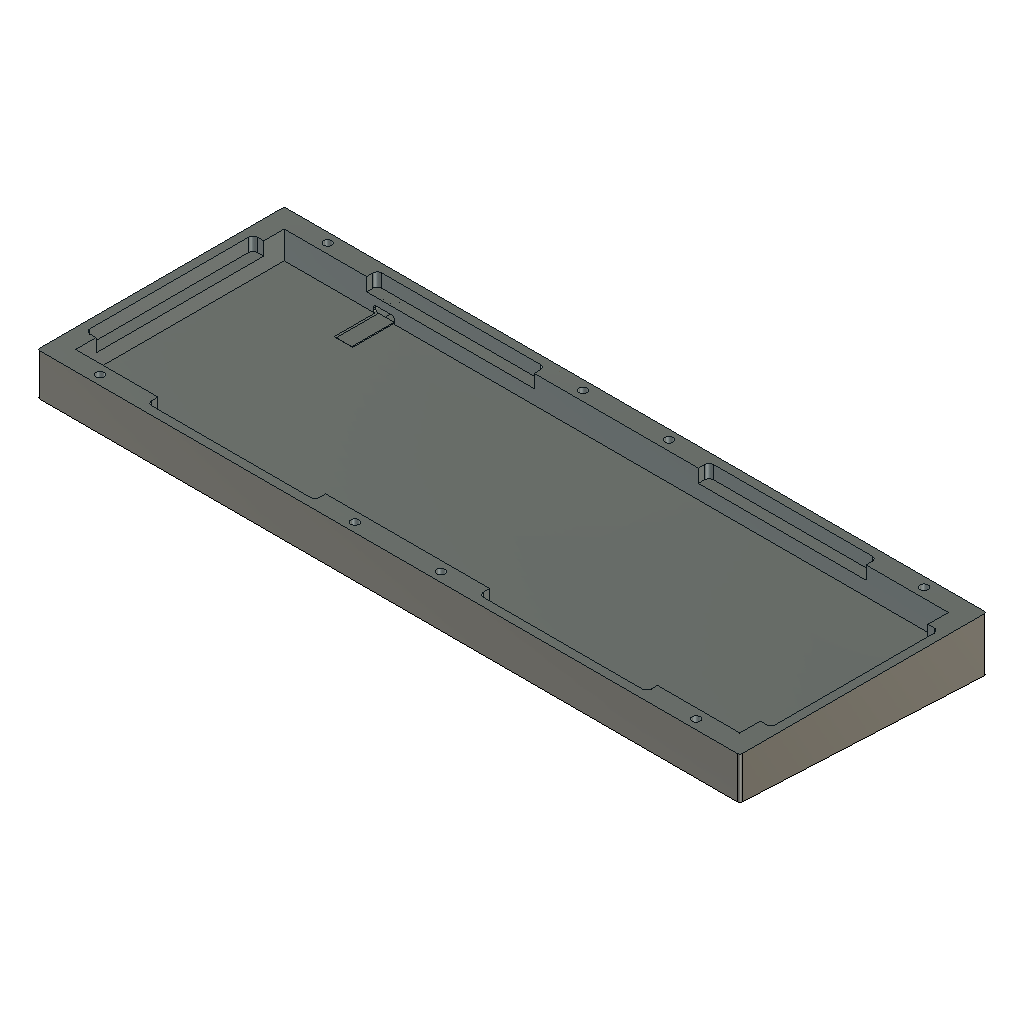
caseBottom (Autodesk Fusion 360 design; units mm, degrees)
Autodesk Fusion 360 part; units mm, degrees
sketch "case" plane through (0, 0, 0) normal (0, 0, 1) x (1, 0, 0)
  line L0 (-12.3912, 10.95) -> (-12.3912, 8.35)
  line L1 (-46.935, 8.35) -> (-12.3912, 8.35)
  line L2 (-46.935, -0.235) -> (-46.935, 8.35)
  line L3 (-46.935, -0.235) -> (-49.535, -0.235)
  arc A0 (-49.535, -0.235) -> (-51.435, -2.135) centre (-49.535, -2.135) ccw
  line L4 (-51.435, -2.135) -> (-51.435, -68.635)
  arc A1 (-51.435, -68.635) -> (-49.535, -70.535) centre (-49.535, -68.635) ccw
  line L5 (-49.535, -70.535) -> (-46.935, -70.535)
  line L6 (-46.935, -70.535) -> (-46.935, -79.12)
  line L7 (-46.935, -79.12) -> (-12.3913, -79.12)
  line L8 (-12.3913, -81.72) -> (-12.3913, -79.12)
  arc A2 (-12.3913, -81.72) -> (-10.4913, -83.62) centre (-10.4913, -81.72) ccw
  line L9 (56.0087, -83.62) -> (-10.4913, -83.62)
  arc A3 (56.0087, -83.62) -> (57.9087, -81.72) centre (56.0087, -81.72) ccw
  line L10 (57.9087, -79.12) -> (57.9087, -81.72)
  line L11 (92.3025, -79.12) -> (57.9087, -79.12)
  line L12 (126.6962, -79.12) -> (92.3025, -79.12)
  line L13 (126.6962, -81.72) -> (126.6962, -79.12)
  arc A4 (126.6962, -81.72) -> (128.5962, -83.62) centre (128.5962, -81.72) ccw
  line L14 (195.0962, -83.62) -> (128.5962, -83.62)
  arc A5 (195.0962, -83.62) -> (196.9963, -81.72) centre (195.0962, -81.72) ccw
  line L15 (196.9963, -79.12) -> (196.9962, -81.72)
  line L16 (196.9963, -79.12) -> (231.54, -79.12)
  line L17 (231.54, -70.535) -> (231.54, -79.12)
  line L18 (231.54, -70.535) -> (234.14, -70.535)
  arc A6 (234.14, -70.535) -> (236.04, -68.635) centre (234.14, -68.635) ccw
  line L19 (236.04, -68.635) -> (236.04, -2.135)
  arc A7 (236.04, -2.135) -> (234.14, -0.235) centre (234.14, -2.135) ccw
  line L20 (234.14, -0.235) -> (231.54, -0.235)
  line L21 (231.54, -0.235) -> (231.54, 8.35)
  line L22 (196.9962, 8.35) -> (231.54, 8.35)
  line L23 (196.9963, 10.95) -> (196.9962, 8.35)
  arc A8 (196.9963, 10.95) -> (195.0962, 12.85) centre (195.0962, 10.95) ccw
  line L24 (128.5963, 12.85) -> (195.0962, 12.85)
  arc A9 (128.5963, 12.85) -> (126.6963, 10.95) centre (128.5963, 10.95) ccw
  line L25 (126.6963, 8.35) -> (126.6963, 10.95)
  line L26 (92.3025, 8.35) -> (126.6963, 8.35)
  line L27 (57.9088, 8.35) -> (92.3025, 8.35)
  line L28 (57.9088, 8.35) -> (57.9088, 10.95)
  arc A10 (57.9088, 10.95) -> (56.0088, 12.85) centre (56.0088, 10.95) ccw
  line L29 (56.0088, 12.85) -> (-10.4912, 12.85)
  arc A11 (-10.4912, 12.85) -> (-12.3912, 10.95) centre (-10.4912, 10.95) ccw
  line L30 (-46.935, -0.235) -> (-46.935, -70.535)
  line L31 (-12.3913, -79.12) -> (57.9087, -79.12)
  line L32 (126.6962, -79.12) -> (196.9963, -79.12)
  line L33 (231.54, -70.535) -> (231.54, -0.235)
  line L34 (196.9962, 8.35) -> (126.6963, 8.35)
  line L35 (57.9088, 8.35) -> (-12.3912, 8.35)
  line L36 (196.9962, 16.35) -> (126.6963, 16.35)
  line L37 (92.3025, 16.35) -> (126.6963, 16.35)
  line L38 (57.9087, 16.35) -> (92.3025, 16.35)
  line L39 (57.9087, 16.35) -> (-12.3912, 16.35)
  line L40 (-53.935, 16.35) -> (-12.3912, 16.35)
  line L41 (-54.935, -0.235) -> (-54.935, 15.35)
  line L42 (-54.935, -0.235) -> (-54.935, -70.535)
  line L43 (-54.935, -70.535) -> (-54.935, -86.12)
  line L44 (-53.935, -87.12) -> (-12.3913, -87.12)
  line L45 (-12.3913, -87.12) -> (57.9087, -87.12)
  line L46 (92.3025, -87.12) -> (57.9087, -87.12)
  line L47 (126.6963, -87.12) -> (92.3025, -87.12)
  line L48 (126.6963, -87.12) -> (196.9963, -87.12)
  line L49 (196.9963, -87.12) -> (238.54, -87.12)
  line L50 (239.54, -70.535) -> (239.54, -86.12)
  line L51 (239.54, -70.535) -> (239.54, -0.235)
  line L52 (239.54, -0.235) -> (239.54, 15.35)
  line L53 (196.9962, 16.35) -> (238.54, 16.35)
  arc A12 (-53.935, 16.35) -> (-54.935, 15.35) centre (-53.935, 15.35) ccw
  arc A13 (-54.935, -86.12) -> (-53.935, -87.12) centre (-53.935, -86.12) ccw
  arc A14 (238.54, -87.12) -> (239.54, -86.12) centre (238.54, -86.12) ccw
  arc A15 (239.54, 15.35) -> (238.54, 16.35) centre (238.54, 15.35) ccw
  dimension "d40" = 8
  dimension "d41" = 8
  dimension "d42" = 8
  dimension "d43" = 8
  dimension "d44" = 8
  dimension "d45" = 8
  dimension "d46" = 8
  dimension "d47" = 8
  dimension "d48" = 8
  dimension "d49" = 8
  dimension "d50" = 8
  dimension "d51" = 8
  dimension "d52" = 8
  dimension "d53" = 8
  dimension "d54" = 8
  dimension "d55" = 8
  dimension "d56" = 8
  dimension "d57" = 8
  dimension "d58" = 1
  dimension "d59" = 1
  dimension "d60" = 1
  dimension "d61" = 1
  constraint coincident L2.start L3.start
  constraint coincident L5.end L6.start
  constraint coincident L7.end L8.end
  constraint coincident L10.start L11.end
  constraint coincident L12.start L13.end
  constraint coincident L15.start L16.start
  constraint coincident L17.start L18.start
  constraint coincident L20.end L21.start
  constraint coincident L22.start L23.end
  constraint coincident L25.start L26.end
  constraint coincident L27.start L28.start
  constraint coincident L0.end L1.end
  constraint tangent L40 A12
  constraint tangent L41 A12
  constraint tangent L43 A13
  constraint tangent L44 A13
  constraint tangent L49 A14
  constraint tangent L50 A14
  constraint tangent L53 A15
  constraint tangent L52 A15
  measures "d40" distance of L34 L36
  measures "d41" distance of L26 L37
  measures "d42" distance of L27 L38
  measures "d43" distance of L35 L39
  measures "d44" distance of L1 L40
  measures "d45" distance of L2 L41
  measures "d46" distance of L30 L42
  measures "d47" distance of L6 L43
  measures "d48" distance of L7 L44
  measures "d49" distance of L31 L45
  measures "d50" distance of L11 L46
  measures "d51" distance of L12 L47
  measures "d52" distance of L32 L48
  measures "d53" distance of L16 L49
  measures "d54" distance of L17 L50
  measures "d55" distance of L33 L51
  measures "d56" distance of L21 L52
  measures "d57" distance of L22 L53
  measures "d58" radius of A12
  measures "d59" radius of A13
  measures "d60" radius of A14
  measures "d61" radius of A15
extrude "Extrude1" add sketch "case" against normal blind 17 contours L0 L28 A10 L29 A11 L35 | L1 L2 L6 L7 L11 L12 L16 L17 L21 L22 L26 L27 L30 L31 L32 L33 L34 L35 | L3 A0 L4 A1 L5 L30 | L23 A8 L24 A9 L25 L34 | L8 A2 L9 A3 L10 L31 | L18 A6 L19 A7 L20 L33 | L13 A4 L14 A5 L15 L32 | L36 L37 L38 L39 L40 L41 L42 L43 L44 L45 L46 L47 L48 L49 L50 L51 L52 L53 A12 A13 A14 A15
sketch "caseSlantCut" plane through (-54.935, 0, 0) normal (-1, 0, 0) x (0, -1, 0)
  line L0 (86.12, 0) -> (-15.35, 0)
  line L1 (-15.35, 0) -> (-15.35, -17)
  line L2 (-15.35, -17) -> (86.12, -17)
  line L3 (86.12, -17) -> (86.12, 0)
  line L4 (-16.35, -17) -> (87.12, -17)
  line L5 (87.12, -17) -> (87.12, -12)
  line L6 (-16.35, -17) -> (87.12, -12)
  point P0 (35.385, -17)
  dimension "d64" = 103.47
  dimension "d65" = 5
  constraint midpoint L4 P0
  constraint coincident L2 P0
  constraint coincident L2 L4.end
  constraint perpendicular L4 L5
  measures "d64" distance of L4.start L4.end
  measures "d65" distance of L4.end L5.end
extrude "Extrude2" cut sketch "caseSlantCut" against normal blind 350 contours L3 L4 L5 L6 | L1 L2 L3 L4 L6
extrude "Extrude3" cut sketch "case" against normal blind 6 contours L1 L2 L6 L7 L11 L12 L16 L17 L21 L22 L26 L27 L30 L31 L32 L33 L34 L35
extrude "Extrude4" add sketch "case" along normal blind 5.55
sketch "usbcCut" plane through (0, 16.35, 0) normal (0, 1, 0) x (-1, 0, 0)
  line L0 (-238.54, 5.55) -> (-238.54, -17)
  line L1 (-238.54, -17) -> (53.935, -17)
  line L2 (53.935, -17) -> (53.935, 5.55)
  line L3 (53.935, 5.55) -> (-238.54, 5.55)
  line L4 (-92.3025, 0.43) -> (5.0505, 0.43) construction
  line L5 (5.0505, 0.43) -> (5.0505, -4.67) construction
  line L6 (8.2905, -5.95) -> (1.8105, -5.95)
  line L7 (0.8805, -5.02) -> (0.8805, -4.32)
  line L8 (1.8105, -3.39) -> (8.2905, -3.39)
  line L9 (9.2205, -4.32) -> (9.2205, -5.02)
  line L10 (9.2205, -5.95) -> (0.8805, -3.39) construction
  line L11 (0.8805, -5.95) -> (9.2205, -3.39) construction
  arc A0 (1.8105, -3.39) -> (0.8805, -4.32) centre (1.8105, -4.32) ccw
  arc A1 (0.8805, -5.02) -> (1.8105, -5.95) centre (1.8105, -5.02) ccw
  arc A2 (9.2205, -4.32) -> (8.2905, -3.39) centre (8.2905, -4.32) ccw
  arc A3 (8.2905, -5.95) -> (9.2205, -5.02) centre (8.2905, -5.02) ccw
  arc A4 (9.4705, -4.32) -> (8.2905, -3.14) centre (8.2905, -4.32) ccw
  line L12 (1.8105, -3.14) -> (8.2905, -3.14)
  arc A5 (1.8105, -3.14) -> (0.6305, -4.32) centre (1.8105, -4.32) ccw
  line L13 (0.6305, -5.02) -> (0.6305, -4.32)
  arc A6 (0.6305, -5.02) -> (1.8105, -6.2) centre (1.8105, -5.02) ccw
  line L14 (8.2905, -6.2) -> (1.8105, -6.2)
  arc A7 (8.2905, -6.2) -> (9.4705, -5.02) centre (8.2905, -5.02) ccw
  line L15 (9.4705, -4.32) -> (9.4705, -5.02)
  arc A8 (12.2705, -4.32) -> (8.2905, -0.34) centre (8.2905, -4.32) ccw
  line L16 (1.8105, -0.34) -> (8.2905, -0.34)
  arc A9 (1.8105, -0.34) -> (-2.1695, -4.32) centre (1.8105, -4.32) ccw
  line L17 (-2.1695, -5.02) -> (-2.1695, -4.32)
  arc A10 (-2.1695, -5.02) -> (1.8105, -9) centre (1.8105, -5.02) ccw
  line L18 (8.2905, -9) -> (1.8105, -9)
  arc A11 (8.2905, -9) -> (12.2705, -5.02) centre (8.2905, -5.02) ccw
  line L19 (12.2705, -4.32) -> (12.2705, -5.02)
  point P0 (5.0505, -4.67)
  dimension "d72" = 97.353
  dimension "d73" = 5.1
  dimension "d75" = 8.34
  dimension "d76" = 2.56
  dimension "d79" = 0.7
  dimension "d80" = 0.7
  dimension "d81" = -0.25
  dimension "d82" = -2.8
  constraint parallel L3 L4
  constraint perpendicular L4 L5
  constraint horizontal L6
  constraint perpendicular L6 L7
  constraint parallel L6 L8
  constraint parallel L7 L9
  constraint coincident L10 P0
  constraint coincident L11 P0
  constraint coincident P0 L5.end
  constraint coincident L10.end L8
  constraint coincident L10.end L7
  constraint tangent L8 A0
  constraint tangent L7 A0
  constraint coincident L11.start L7
  constraint coincident L11.start L6
  constraint tangent L7 A1
  constraint tangent L6 A1
  constraint equal A0 A1
  constraint coincident L11.end L8
  constraint coincident L11.end L9
  constraint tangent L8 A2
  constraint tangent L9 A2
  constraint equal A0 A2
  constraint coincident L10.start L9
  constraint coincident L10.start L6
  constraint tangent L9 A3
  constraint tangent L6 A3
  measures "d72" distance of L4.start L4.end
  measures "d73" distance of L4 P0
  measures "d75" distance of L10.end L11.end
  measures "d76" distance of L11.start L10.end
  measures "d79" distance of L7.end L7.start
  measures "d80" distance of L9.start L9.end
extrude "Extrude5" cut sketch "usbcCut" against normal blind 20 contours L6 L7 L8 L9 A0 A1 A2 A3 | A4 L12 A5 L13 A6 L14 A7 L15
extrude "Extrude6" cut sketch "usbcCut" against normal blind 25 contours L6 L7 L8 L9 A0 A1 A2 A3 | A4 L12 A5 L13 A6 L14 A7 L15
sketch "Sketch4" plane through (0, 16.35, 0) normal (0, 1, 0) x (-1, 0, 0)
sketch "Sketch5" plane through (0, 0, 0) normal (0, 0, 1) x (1, 0, 0)
  line L0 (-8.9475, 8.35) -> (-8.9475, 9.29)
  dimension "d87" = 0.94
  constraint vertical L0
  measures "d87" distance of L0.start L0.end
extrude "Extrude7" cut sketch "usbcCut" against normal blind 7.06 contours A8 L16 A9 L17 A10 L18 A11 L19
sketch "Sketch6" plane through (0, 0, 5.55) normal (0, 0, 1) x (-1, 0, 0)
  line L0 (-57.9088, -10.95) -> (-57.9088, -8.35)
  line L1 (-57.9088, -8.35) -> (-126.6963, -8.35)
  line L2 (-126.6963, -8.35) -> (-126.6963, -10.95)
  arc A0 (-128.5963, -12.85) -> (-126.6963, -10.95) centre (-128.5963, -10.95) ccw
  line L3 (-128.5963, -12.85) -> (-195.0962, -12.85)
  arc A1 (-196.9963, -10.95) -> (-195.0962, -12.85) centre (-195.0963, -10.95) ccw
  line L4 (-196.9963, -10.95) -> (-196.9962, -8.35)
  line L5 (-196.9962, -8.35) -> (-231.54, -8.35)
  line L6 (-231.54, -8.35) -> (-231.54, 0.235)
  line L7 (-231.54, 0.235) -> (-234.14, 0.235)
  arc A2 (-236.04, 2.135) -> (-234.14, 0.235) centre (-234.14, 2.135) ccw
  line L8 (-236.04, 2.135) -> (-236.04, 68.635)
  arc A3 (-234.14, 70.535) -> (-236.04, 68.635) centre (-234.14, 68.635) ccw
  line L9 (-234.14, 70.535) -> (-231.54, 70.535)
  line L10 (-231.54, 70.535) -> (-231.54, 79.12)
  line L11 (-231.54, 79.12) -> (-196.9963, 79.12)
  line L12 (-196.9963, 79.12) -> (-196.9962, 81.72)
  arc A4 (-195.0962, 83.62) -> (-196.9962, 81.72) centre (-195.0962, 81.72) ccw
  line L13 (-195.0962, 83.62) -> (-128.5962, 83.62)
  arc A5 (-126.6962, 81.72) -> (-128.5962, 83.62) centre (-128.5962, 81.72) ccw
  line L14 (-126.6962, 81.72) -> (-126.6962, 79.12)
  line L15 (-126.6962, 79.12) -> (-57.9087, 79.12)
  line L16 (-57.9087, 79.12) -> (-57.9087, 81.72)
  arc A6 (-56.0087, 83.62) -> (-57.9087, 81.72) centre (-56.0087, 81.72) ccw
  line L17 (-56.0087, 83.62) -> (10.4913, 83.62)
  arc A7 (12.3913, 81.72) -> (10.4913, 83.62) centre (10.4913, 81.72) ccw
  line L18 (12.3913, 81.72) -> (12.3913, 79.12)
  line L19 (12.3913, 79.12) -> (46.935, 79.12)
  line L20 (46.935, 79.12) -> (46.935, 70.535)
  line L21 (46.935, 70.535) -> (49.535, 70.535)
  arc A8 (51.435, 68.635) -> (49.535, 70.535) centre (49.535, 68.635) ccw
  line L22 (51.435, 68.635) -> (51.435, 2.135)
  arc A9 (49.535, 0.235) -> (51.435, 2.135) centre (49.535, 2.135) ccw
  line L23 (49.535, 0.235) -> (46.935, 0.235)
  line L24 (46.935, 0.235) -> (46.935, -8.35)
  line L25 (46.935, -8.35) -> (12.3912, -8.35)
  line L26 (12.3912, -8.35) -> (12.3912, -10.95)
  arc A10 (10.4912, -12.85) -> (12.3912, -10.95) centre (10.4912, -10.95) ccw
  line L27 (10.4912, -12.85) -> (-56.0088, -12.85)
  arc A11 (-57.9088, -10.95) -> (-56.0088, -12.85) centre (-56.0088, -10.95) ccw
  line L28 (-239.54, 86.12) -> (-239.54, -15.35)
  arc A12 (-239.54, -15.35) -> (-238.54, -16.35) centre (-238.54, -15.35) ccw
  line L29 (-238.54, -16.35) -> (53.935, -16.35)
  arc A13 (53.935, -16.35) -> (54.935, -15.35) centre (53.935, -15.35) ccw
  line L30 (54.935, -15.35) -> (54.935, 86.12)
  arc A14 (54.935, 86.12) -> (53.935, 87.12) centre (53.935, 86.12) ccw
  line L31 (53.935, 87.12) -> (-238.54, 87.12)
  arc A15 (-238.54, 87.12) -> (-239.54, 86.12) centre (-238.54, 86.12) ccw
  line L32 (-92.3025, -16.35) -> (-92.3025, 87.12) construction
  line L33 (32.6975, -16.35) -> (32.6975, 87.12) construction
  line L34 (-217.3025, -16.35) -> (-217.3025, 87.12) construction
  line L35 (-92.3025, 79.12) -> (-92.3025, 87.12) construction
  line L36 (32.6975, 83.12) -> (-217.3025, 83.12) construction
  line L37 (-92.3025, -16.35) -> (-92.3025, -8.35) construction
  line L38 (-217.3025, -12.4391) -> (32.6975, -12.4391) construction
  line L39 (-74.3025, -16.35) -> (-74.3025, 87.12) construction
  line L40 (-110.3025, 87.12) -> (-110.3025, -16.35) construction
  circle A16 centre (-74.3025, -12.4391) radius 1.7
  circle A17 centre (32.6975, -12.4391) radius 1.7
  circle A18 centre (32.6975, -12.4391) radius 2.85
  circle A19 centre (-74.3025, -12.4391) radius 2.85
  circle A20 centre (-110.3025, -12.4391) radius 2.85
  circle A21 centre (-110.3025, -12.4391) radius 1.7
  circle A22 centre (-217.3025, -12.4391) radius 2.85
  circle A23 centre (-217.3025, -12.4391) radius 1.7
  line L41 (-239.54, 35.385) -> (54.935, 35.385)
  circle A24 centre (32.6975, 83.2091) radius 1.7
  circle A25 centre (32.6975, 83.2091) radius 2.85
  circle A26 centre (-74.3025, 83.2091) radius 2.85
  circle A27 centre (-74.3025, 83.2091) radius 1.7
  circle A28 centre (-110.3025, 83.2091) radius 1.7
  circle A29 centre (-110.3025, 83.2091) radius 2.85
  circle A30 centre (-217.3025, 83.2091) radius 2.85
  circle A31 centre (-217.3025, 83.2091) radius 1.7
  point P0 (-92.3025, 83.12)
  point P1 (-92.3025, -12.4391)
  point P2 (-92.3025, 35.385)
  dimension "d90" = 125
  dimension "d91" = 125
  dimension "d98" = 18
  dimension "d99" = 18
  dimension "d100" = 3.4
  dimension "d103" = 3.4
  dimension "d104" = 5.7
  dimension "d105" = 5.7
  constraint midpoint L29 L32.start
  constraint midpoint L31 L32.end
  constraint coincident L29 L33.start
  constraint perpendicular L29 L33
  constraint coincident L31 L33.end
  constraint coincident L29 L34.start
  constraint perpendicular L29 L34
  constraint coincident L31 L34.end
  constraint coincident L15 L35.start
  constraint coincident L31 L32.end
  constraint perpendicular L31 L35
  constraint midpoint L36 P0
  constraint coincident L35 P0
  constraint coincident L34 L36.end
  constraint perpendicular L34 L36
  constraint coincident L33 L36.start
  constraint coincident L29 L32.start
  constraint coincident L1 L37.end
  constraint perpendicular L1 L37
  constraint midpoint L38 P1
  constraint coincident L37 P1
  constraint coincident L33 L38.end
  constraint perpendicular L33 L38
  constraint coincident L34 L38.start
  constraint coincident L29 L39.start
  constraint perpendicular L29 L39
  constraint coincident L31 L39.end
  constraint coincident L31 L40.start
  constraint perpendicular L31 L40
  constraint coincident L29 L40.end
  constraint coincident L39 A16.centre
  constraint coincident L38 A16.centre
  constraint coincident L38.end A17.centre
  constraint concentric A17 A18
  constraint concentric A16 A19
  constraint symmetric L32 A16 A21
  constraint symmetric L32 A17 A23
  constraint symmetric L32 A18 A22
  constraint symmetric L32 A19 A20
  constraint midpoint L41 P2
  constraint coincident L32 P2
  constraint coincident L30 L41.end
  constraint perpendicular L30 L41
  constraint symmetric A16 L41 A27
  constraint symmetric A17 L41 A24
  constraint symmetric A18 L41 A25
  constraint symmetric A19 L41 A26
  constraint symmetric A20 L41 A29
  constraint symmetric A21 L41 A28
  constraint symmetric A22 L41 A30
  constraint symmetric A23 L41 A31
  measures "d90" distance of L32 L33
  measures "d91" distance of L32 L34
  measures "d98" distance of L32 L39
  measures "d99" distance of L32 L40
  measures "d100" diameter of A16
  measures "d103" diameter of A17
  measures "d104" diameter of A18
  measures "d105" diameter of A19
fillet "Fillet1" radius 0.5 8 edges at (-11.1048, 16.35, -1.5057) (-12.2705, 16.35, -4.67) (-11.1048, 16.35, -7.8343) (-5.0505, 16.35, -9) (1.0038, 16.35, -7.8343) (2.1695, 16.35, -4.67) (1.0038, 16.35, -1.5057) (-5.0505, 16.35, -0.34)
extrude "Extrude8" cut sketch "Sketch6" against normal blind 40 contours A16 | A17 | A21 | A23 | A24 | A27 | A28 | A31
extrude "Extrude9" cut sketch "Sketch6" against normal blind 30 from surface at -15 contours A18 | A19 | A20 | A22 | A25 | A26 | A29 | A30
extrude "Extrude10" cut sketch "caseSlantCut" against normal blind 420 contours L3 L4 L5 L6 | L1 L2 L3 L4 L6 | L1 L4 L6
sketch "Sketch7" plane through (0, -0.7815, -16.1722) normal (0, -0.048267, -0.998834) x (1, 0, 0)
  line L0 (239.54, -16.1503) -> (239.54, 85.4381)
  ellipse E0 centre (238.54, 85.4381) end of major axis (238.54, 86.4393) minor radius 1 (239.54, 85.4381) -> (238.54, 86.4393) ccw
  line L1 (238.54, 86.4393) -> (-53.935, 86.4393)
  ellipse E1 centre (-53.935, 85.4381) end of major axis (-53.935, 84.4369) minor radius 1 (-53.935, 86.4393) -> (-54.935, 85.4381) ccw
  line L2 (-54.935, 85.4381) -> (-54.935, -16.1503)
  ellipse E2 centre (-53.935, -16.1503) end of major axis (-53.935, -17.1515) minor radius 1 (-54.935, -16.1503) -> (-53.935, -17.1515) ccw
  line L3 (-53.935, -17.1515) -> (238.54, -17.1515)
  ellipse E3 centre (238.54, -16.1503) end of major axis (238.54, -15.1491) minor radius 1 (238.54, -17.1515) -> (239.54, -16.1503) ccw
  ellipse E4 centre (74.3025, 82.5238) end of major axis (74.3025, 79.6705) minor radius 2.85
  ellipse E5 centre (217.3025, -13.236) end of major axis (217.3025, -16.0893) minor radius 2.85
  ellipse E6 centre (-32.6975, -13.236) end of major axis (-32.6975, -16.0893) minor radius 2.85
  ellipse E7 centre (217.3025, 82.5238) end of major axis (217.3025, 79.6705) minor radius 2.85
  ellipse E8 centre (-32.6975, 82.5238) end of major axis (-32.6975, 79.6705) minor radius 2.85
  ellipse E9 centre (110.3025, -13.236) end of major axis (110.3025, -16.0893) minor radius 2.85
  ellipse E10 centre (74.3025, -13.236) end of major axis (74.3025, -16.0893) minor radius 2.85
  ellipse E11 centre (110.3025, 82.5238) end of major axis (110.3025, 79.6705) minor radius 2.85
  line L4 (229.54, -7.1515) -> (229.54, 76.4393) construction
  line L5 (229.54, 76.4393) -> (-44.935, 76.4393) construction
  line L6 (-44.935, 76.4393) -> (-44.935, -7.1515) construction
  line L7 (-44.935, -7.1515) -> (229.54, -7.1515) construction
  circle A0 centre (229.54, 76.4393) radius 4
  circle A1 centre (-44.935, 76.4393) radius 4
  circle A2 centre (229.54, -7.1515) radius 4
  circle A3 centre (-44.935, -7.1515) radius 4
  dimension "d113" = -10
  dimension "d114" = 8
  dimension "d115" = 8
  dimension "d116" = 8
  dimension "d117" = 8
  constraint coincident L4.end L5.start
  constraint coincident L5.end L6.start
  constraint coincident L4.start L7.end
  constraint coincident L6.end L7.start
  measures "d114" diameter of A0
  measures "d115" diameter of A1
  measures "d116" diameter of A2
  measures "d117" diameter of A3
extrude "Extrude11" cut sketch "Sketch7" against normal blind 1 contours A0 | A1 | A2 | A3
chamfer "Chamfer1" distance 1 angle 45 1 edges at (-48.6643, 4.9169, -16.4475) tangent chain off
chamfer "Chamfer2" distance 1 angle 45 3 edges at (-48.6643, -78.5764, -12.4129) (225.8107, -78.5764, -12.4129) (225.8107, 4.9169, -16.4475) tangent chain off
sketch "Sketch8" plane through (0, 0, 5.55) normal (0, 0, 1) x (-1, 0, 0)
  line L0 (-239.54, 86.12) -> (-239.54, -15.35)
  arc A0 (-239.54, -15.35) -> (-238.54, -16.35) centre (-238.54, -15.35) ccw
  line L1 (-238.54, -16.35) -> (53.935, -16.35)
  arc A1 (53.935, -16.35) -> (54.935, -15.35) centre (53.935, -15.35) ccw
  line L2 (54.935, -15.35) -> (54.935, 86.12)
  arc A2 (54.935, 86.12) -> (53.935, 87.12) centre (53.935, 86.12) ccw
  line L3 (53.935, 87.12) -> (-238.54, 87.12)
  arc A3 (-238.54, 87.12) -> (-239.54, 86.12) centre (-238.54, 86.12) ccw
  line L4 (-57.9088, -10.95) -> (-57.9088, -8.35)
  line L5 (-57.9088, -8.35) -> (-126.6963, -8.35)
  line L6 (-126.6963, -8.35) -> (-126.6963, -10.95)
  arc A4 (-128.5963, -12.85) -> (-126.6963, -10.95) centre (-128.5963, -10.95) ccw
  line L7 (-128.5963, -12.85) -> (-195.0962, -12.85)
  arc A5 (-196.9963, -10.95) -> (-195.0962, -12.85) centre (-195.0963, -10.95) ccw
  line L8 (-196.9963, -10.95) -> (-196.9962, -8.35)
  line L9 (-196.9962, -8.35) -> (-231.54, -8.35)
  line L10 (-231.54, -8.35) -> (-231.54, 0.235)
  line L11 (-231.54, 0.235) -> (-234.14, 0.235)
  arc A6 (-236.04, 2.135) -> (-234.14, 0.235) centre (-234.14, 2.135) ccw
  line L12 (-236.04, 2.135) -> (-236.04, 68.635)
  arc A7 (-234.14, 70.535) -> (-236.04, 68.635) centre (-234.14, 68.635) ccw
  line L13 (-234.14, 70.535) -> (-231.54, 70.535)
  line L14 (-231.54, 70.535) -> (-231.54, 79.12)
  line L15 (-231.54, 79.12) -> (-196.9963, 79.12)
  line L16 (-196.9963, 79.12) -> (-196.9962, 81.72)
  arc A8 (-195.0962, 83.62) -> (-196.9962, 81.72) centre (-195.0962, 81.72) ccw
  line L17 (-195.0962, 83.62) -> (-128.5962, 83.62)
  arc A9 (-126.6962, 81.72) -> (-128.5962, 83.62) centre (-128.5962, 81.72) ccw
  line L18 (-126.6962, 81.72) -> (-126.6962, 79.12)
  line L19 (-126.6962, 79.12) -> (-57.9087, 79.12)
  line L20 (-57.9087, 79.12) -> (-57.9087, 81.72)
  arc A10 (-56.0087, 83.62) -> (-57.9087, 81.72) centre (-56.0087, 81.72) ccw
  line L21 (-56.0087, 83.62) -> (10.4913, 83.62)
  arc A11 (12.3913, 81.72) -> (10.4913, 83.62) centre (10.4913, 81.72) ccw
  line L22 (12.3913, 81.72) -> (12.3913, 79.12)
  line L23 (12.3913, 79.12) -> (46.935, 79.12)
  line L24 (46.935, 79.12) -> (46.935, 70.535)
  line L25 (46.935, 70.535) -> (49.535, 70.535)
  arc A12 (51.435, 68.635) -> (49.535, 70.535) centre (49.535, 68.635) ccw
  line L26 (51.435, 68.635) -> (51.435, 2.135)
  arc A13 (49.535, 0.235) -> (51.435, 2.135) centre (49.535, 2.135) ccw
  line L27 (49.535, 0.235) -> (46.935, 0.235)
  line L28 (46.935, 0.235) -> (46.935, -8.35)
  line L29 (46.935, -8.35) -> (12.3912, -8.35)
  line L30 (12.3912, -8.35) -> (12.3912, -10.95)
  arc A14 (10.4912, -12.85) -> (12.3912, -10.95) centre (10.4912, -10.95) ccw
  line L31 (10.4912, -12.85) -> (-56.0088, -12.85)
  arc A15 (-57.9088, -10.95) -> (-56.0088, -12.85) centre (-56.0088, -10.95) ccw
  circle A16 centre (32.6975, -12.4391) radius 1.7
  circle A17 centre (-217.3025, 83.2091) radius 1.7
  circle A18 centre (32.6975, 83.2091) radius 1.7
  circle A19 centre (-217.3025, -12.4391) radius 1.7
  circle A20 centre (-110.3025, -12.4391) radius 1.7
  circle A21 centre (-110.3025, 83.2091) radius 1.7
  circle A22 centre (-74.3025, 83.2091) radius 1.7
  circle A23 centre (-74.3025, -12.4391) radius 1.7
sketch "Sketch9" plane through (0, -0.7815, -16.1722) normal (0, -0.048267, -0.998834) x (1, 0, 0)
  circle A0 centre (229.54, 76.4393) radius 5
  circle A1 centre (-44.935, -7.1515) radius 5
  ellipse E0 centre (110.3025, 82.5238) end of major axis (110.3025, 79.6705) minor radius 2.85
  ellipse E1 centre (74.3025, -13.236) end of major axis (74.3025, -16.0893) minor radius 2.85
  ellipse E2 centre (110.3025, -13.236) end of major axis (110.3025, -16.0893) minor radius 2.85
  ellipse E3 centre (-32.6975, 82.5238) end of major axis (-32.6975, 79.6705) minor radius 2.85
  ellipse E4 centre (217.3025, 82.5238) end of major axis (217.3025, 79.6705) minor radius 2.85
  ellipse E5 centre (-32.6975, -13.236) end of major axis (-32.6975, -16.0893) minor radius 2.85
  ellipse E6 centre (217.3025, -13.236) end of major axis (217.3025, -16.0893) minor radius 2.85
  ellipse E7 centre (74.3025, 82.5238) end of major axis (74.3025, 79.6705) minor radius 2.85
  line L0 (239.54, -16.1503) -> (239.54, 85.4381)
  ellipse E8 centre (238.54, 85.4381) end of major axis (238.54, 86.4393) minor radius 1 (239.54, 85.4381) -> (238.54, 86.4393) ccw
  line L1 (238.54, 86.4393) -> (-53.935, 86.4393)
  ellipse E9 centre (-53.935, 85.4381) end of major axis (-53.935, 84.4369) minor radius 1 (-53.935, 86.4393) -> (-54.935, 85.4381) ccw
  line L2 (-54.935, 85.4381) -> (-54.935, -16.1503)
  ellipse E10 centre (-53.935, -16.1503) end of major axis (-53.935, -17.1515) minor radius 1 (-54.935, -16.1503) -> (-53.935, -17.1515) ccw
  line L3 (-53.935, -17.1515) -> (238.54, -17.1515)
  ellipse E11 centre (238.54, -16.1503) end of major axis (238.54, -15.1491) minor radius 1 (238.54, -17.1515) -> (239.54, -16.1503) ccw
  circle A2 centre (-44.935, 76.4393) radius 5
  circle A3 centre (229.54, -7.1515) radius 5
  line L4 (93.1245, 38.1078) -> (101.4798, 45.8561)
  line L5 (101.4798, 45.8561) -> (106.8692, 43.3217)
  arc A4 (108.4785, 43.9019) -> (106.8692, 43.3217) centre (107.3839, 44.416) cw
  arc A5 (107.8982, 45.5105) -> (108.4785, 43.9019) centre (107.3838, 44.416) cw
  line L6 (107.8982, 45.5105) -> (101.7711, 48.3922)
  arc A6 (100.4342, 48.1851) -> (101.7711, 48.3922) centre (101.2561, 47.2978) cw
  line L7 (100.4342, 48.1851) -> (92.3025, 40.6439)
  line L8 (92.3025, 40.6439) -> (84.1708, 48.1851)
  arc A7 (82.8339, 48.3922) -> (84.1708, 48.1851) centre (83.3489, 47.2978) cw
  line L9 (82.8339, 48.3922) -> (76.7068, 45.5105)
  arc A8 (76.1265, 43.9019) -> (76.7068, 45.5105) centre (77.2212, 44.416) cw
  arc A9 (77.7358, 43.3217) -> (76.1265, 43.9019) centre (77.2211, 44.416) cw
  line L10 (77.7358, 43.3217) -> (83.1252, 45.8561)
  line L11 (83.1252, 45.8561) -> (91.4805, 38.1078)
  arc A10 (93.1245, 38.1078) -> (91.4805, 38.1079) centre (92.3025, 38.9951) cw
  arc A11 (80.6495, 18.5799) -> (78.9684, 17.6843) centre (79.4584, 18.7901) cw
  line L12 (80.6495, 18.5799) -> (81.9956, 26.2295)
  line L13 (81.9956, 26.2295) -> (88.8893, 27.8155)
  arc A12 (88.9575, 30.1549) -> (88.8893, 27.8155) centre (88.6177, 28.9941) cw
  line L14 (88.9575, 30.1549) -> (82.6178, 32.0095)
  line L15 (82.6178, 32.0095) -> (80.1653, 40.0964)
  arc A13 (77.8176, 39.961) -> (80.1653, 40.0964) centre (79.0078, 39.7456) cw
  line L16 (77.8176, 39.961) -> (76.2993, 31.576)
  line L17 (76.2993, 31.576) -> (70.6108, 31.1977)
  arc A14 (70.1741, 28.8976) -> (70.6108, 31.1977) centre (70.6913, 29.9909) cw
  line L18 (70.1741, 28.8976) -> (76.4099, 25.9494)
  line L19 (76.4099, 25.9494) -> (78.2858, 18.4946)
  arc A15 (78.9684, 17.6843) -> (78.2858, 18.4946) centre (79.4586, 18.79) cw
  line L20 (79.2496, 24.5769) -> (78.616, 27.0935)
  arc A16 (77.9602, 27.8919) -> (78.616, 27.0935) centre (77.443, 26.7986) cw
  line L21 (77.9602, 27.8919) -> (75.4188, 29.0934)
  line L22 (75.4188, 29.0934) -> (77.4011, 29.2252)
  arc A17 (78.5111, 30.2164) -> (77.4011, 29.2252) centre (77.321, 30.432) cw
  line L23 (78.5111, 30.2164) -> (79.3048, 34.5995)
  line L24 (79.3048, 34.5995) -> (80.4929, 30.682)
  arc A18 (81.3109, 29.8722) -> (80.4929, 30.682) centre (81.6503, 31.0331) cw
  line L25 (81.3109, 29.8722) -> (83.8327, 29.1342)
  line L26 (83.8327, 29.1342) -> (80.6727, 28.4072)
  arc A19 (79.7529, 27.4382) -> (80.6727, 28.4072) centre (80.944, 27.2285) cw
  line L27 (79.7529, 27.4382) -> (79.2496, 24.5769)
  arc A20 (120.2677, 5.0422) -> (118.8621, 4.0681) centre (119.0778, 5.2581) cw
  line L28 (120.2677, 5.0422) -> (121.3881, 11.2273)
  arc A21 (120.0812, 12.6469) -> (121.3881, 11.2273) centre (120.198, 11.4431) cw
  line L29 (120.0812, 12.6469) -> (116.6411, 12.3131)
  line L30 (116.6411, 12.3131) -> (121.4232, 17.1319)
  arc A22 (121.4165, 18.8419) -> (121.4232, 17.1319) centre (120.5645, 17.9835) cw
  arc A23 (119.706, 18.8357) -> (121.4165, 18.8419) centre (120.5643, 17.9837) cw
  line L31 (119.706, 18.8357) -> (112.5628, 11.6371)
  arc A24 (113.5379, 9.5814) -> (112.5628, 11.6371) centre (113.4214, 10.7853) cw
  line L32 (113.5379, 9.5814) -> (118.7231, 10.0848)
  line L33 (118.7231, 10.0848) -> (117.8875, 5.4737)
  arc A25 (118.8621, 4.0681) -> (117.8875, 5.4737) centre (119.0775, 5.2581) cw
  arc A26 (124.2294, -2.1735) -> (123.4822, -3.2097) centre (123.0227, -2.0909) cw
  line L34 (124.2294, -2.1735) -> (125.871, 22.0043)
  line L35 (125.871, 22.0043) -> (131.5288, 38.6047)
  arc A27 (131.469, 39.5282) -> (131.5288, 38.6047) centre (130.3838, 38.9942) cw
  line L36 (131.469, 39.5282) -> (124.8592, 52.9729)
  arc A28 (124.4593, 53.4359) -> (124.8592, 52.9729) centre (123.7738, 52.4394) cw
  line L37 (124.4593, 53.4359) -> (110.0375, 63.3501)
  arc A29 (109.48, 63.5564) -> (110.0375, 63.3501) centre (109.3519, 62.3538) cw
  line L38 (109.48, 63.5564) -> (92.4293, 65.3595)
  arc A30 (92.1757, 65.3595) -> (92.4293, 65.3595) centre (92.3025, 64.1566) cw
  line L39 (92.1757, 65.3595) -> (75.125, 63.5564)
  arc A31 (74.5675, 63.3501) -> (75.125, 63.5564) centre (75.2531, 62.3538) cw
  line L40 (74.5675, 63.3501) -> (60.1457, 53.4359)
  arc A32 (59.7458, 52.9729) -> (60.1457, 53.4359) centre (60.8312, 52.4394) cw
  line L41 (59.7458, 52.9729) -> (53.136, 39.5282)
  arc A33 (53.0762, 38.6047) -> (53.136, 39.5282) centre (54.2212, 38.9942) cw
  line L42 (53.0762, 38.6047) -> (58.734, 22.0043)
  line L43 (58.734, 22.0043) -> (60.3756, -2.1735)
  arc A34 (62.3834, -2.9971) -> (60.3756, -2.1735) centre (61.5823, -2.0909) cw
  line L44 (62.3834, -2.9971) -> (78.8019, 11.516)
  line L45 (78.8019, 11.516) -> (92.16, 9.9272)
  arc A35 (92.445, 9.9272) -> (92.16, 9.9272) centre (92.3025, 11.1282) cw
  line L46 (92.445, 9.9272) -> (105.8031, 11.516)
  line L47 (105.8031, 11.516) -> (122.2216, -2.9971)
  arc A36 (123.4822, -3.2097) -> (122.2216, -2.9971) centre (123.0227, -2.0909) cw
  line L48 (121.9823, 0.442) -> (106.9991, 13.6868)
  arc A37 (106.0551, 13.9812) -> (106.9991, 13.6868) centre (106.1984, 12.7803) cw
  line L49 (106.0551, 13.9812) -> (92.3025, 12.3467)
  line L50 (92.3025, 12.3467) -> (78.5499, 13.9812)
  arc A38 (77.6059, 13.6868) -> (78.5499, 13.9812) centre (78.4066, 12.7803) cw
  line L51 (77.6059, 13.6868) -> (62.6227, 0.442)
  line L52 (62.6227, 0.442) -> (61.1362, 22.3263)
  arc A39 (61.074, 22.6349) -> (61.1362, 22.3263) centre (59.9296, 22.2437) cw
  line L53 (61.074, 22.6349) -> (55.5272, 38.9102)
  line L54 (55.5272, 38.9102) -> (61.7771, 51.6219)
  line L55 (61.7771, 51.6219) -> (75.6848, 61.1834)
  line L56 (75.6848, 61.1834) -> (92.3025, 62.9407)
  line L57 (92.3025, 62.9407) -> (108.9202, 61.1834)
  line L58 (108.9202, 61.1834) -> (122.8279, 51.6219)
  line L59 (122.8279, 51.6219) -> (129.0778, 38.9102)
  line L60 (129.0778, 38.9102) -> (123.531, 22.6349)
  arc A40 (123.4688, 22.3263) -> (123.531, 22.6349) centre (124.6754, 22.2437) cw
  line L61 (123.4688, 22.3263) -> (121.9823, 0.442)
extrude "Extrude12" cut sketch "Sketch9" against normal blind 0.8 contours L4 L5 A4 A5 L6 A6 L7 L8 A7 L9 A8 A9 L10 L11 A10 | A11 L12 L13 A12 L14 L15 A13 L16 L17 A14 L18 L19 A15 | A20 L28 A21 L29 L30 A22 A23 L31 A24 L32 L33 A25 | A26 L34 L35 A27 L36 A28 L37 A29 L38 A30 L39 A31 L40 A32 L41 A33 L42 L43 A34 L44 L45 A35 L46 L47 A36
equation "d73 = 3.5 mm + 1.6 mm"
